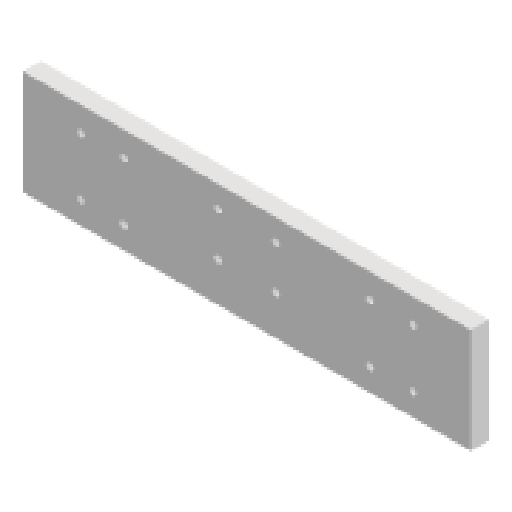
# Autodesk Inventor part: BodyBackLock
Saved by Autodesk Inventor 2025.2 (Build 292293000, 293)
## iProperties
Created: 2025-06-20
Part Number: BodyBackLock
Material: Generic
Document SubType Name: Modeling
Designer: ricoa
Density: 1 g/cm^3
Appearance: Default
Author: ricoa
Autodesk Inventor part; units mm, degrees
ref_plane "YZ Plane" through (0, 0, 0) normal (1, 0, 0) x (0, 1, 0)
ref_plane "XZ Plane" through (0, 0, 0) normal (0, 1, 0) x (-1, 0, 0)
ref_plane "XY Plane" through (0, 0, 0) normal (0, 0, 1) x (1, 0, 0)
sketch "Sketch1" plane through (0, 0, 0) normal (0, 0, 1) x (1, 0, 0)
  line L0 (0, 0) -> (-8, 0)
  line L1 (-8, 0) -> (-8, 8.75)
  circle A0 centre (-8, 8.75) radius 1
  line L2 (0, 0) -> (0, 20.6668)
  line L3 (0, 0) -> (-30.575, 0)
  line L4 (-57, 14.75) -> (57, 14.75)
  line L5 (57, 14.75) -> (57, -14.75)
  line L6 (-57, -14.75) -> (-57, 14.75)
  line L7 (-57, 14.75) -> (57, -14.75) construction
  line L8 (57, 14.75) -> (-57, -14.75) construction
  circle A1 centre (8, 8.75) radius 1
  circle A2 centre (-8, -3.25) radius 1
  circle A3 centre (8, -3.25) radius 1
  line L9 (57, 0) -> (46, 0)
  line L10 (46, 0) -> (46, 8)
  line L11 (46, 8) -> (34, 8)
  circle A4 centre (46, 8) radius 1
  circle A5 centre (34, 8) radius 1
  circle A6 centre (46, -8) radius 1
  circle A7 centre (34, -8) radius 1
  circle A8 centre (-46, 8) radius 1
  circle A9 centre (-34, 8) radius 1
  circle A10 centre (-46, -8) radius 1
  circle A11 centre (-34, -8) radius 1
  line L12 (8, 0) -> (8, -3.25) construction
  line L13 (8, -3.25) -> (-8, -3.25) construction
  line L14 (-8, -3.25) -> (-8, 0)
  line L15 (57, 14.75) -> (62, 14.75) projected
  line L16 (-62, 14.75) -> (-57, 14.75) projected
  line L17 (57, -49.25) -> (57, 14.75) projected
  line L18 (52, -19.25) -> (42, -19.25) projected
  line L19 (42, -19.25) -> (42, -14.25) projected
  line L20 (52, -19.25) -> (52, -14.25) projected
  line L21 (42, -19.25) -> (42, -14.25) projected
  line L22 (52, -19.25) -> (52, -14.25) projected
  line L23 (32, -19.25) -> (22, -19.25) projected
  line L24 (22, -19.25) -> (22, -14.25) projected
  line L25 (32, -19.25) -> (32, -14.25) projected
  line L26 (12, -19.25) -> (2, -19.25) projected
  line L27 (2, -19.25) -> (2, -14.25) projected
  line L28 (12, -19.25) -> (12, -14.25) projected
  line L29 (-22, -19.25) -> (-32, -19.25) projected
  line L30 (-32, -19.25) -> (-32, -14.25) projected
  line L31 (-22, -19.25) -> (-22, -14.25) projected
  line L32 (-42, -19.25) -> (-52, -19.25) projected
  line L33 (-52, -19.25) -> (-52, -14.25) projected
  line L34 (-42, -19.25) -> (-42, -14.25) projected
  line L35 (-57, -49.25) -> (-57, 14.75) projected
  line L36 (12, -19.25) -> (2, -19.25) projected
  line L37 (2, -19.25) -> (2, -14.25) projected
  line L38 (12, -19.25) -> (12, -14.25) projected
  line L39 (32, -19.25) -> (22, -19.25) projected
  line L40 (22, -19.25) -> (22, -14.25) projected
  line L41 (32, -19.25) -> (32, -14.25) projected
  line L42 (52, -19.25) -> (42, -19.25) projected
  line L43 (42, -19.25) -> (42, -14.25) projected
  line L44 (52, -19.25) -> (52, -14.25) projected
  line L45 (52, -14.25) -> (57, -14.25)
  line L46 (42, -14.25) -> (32, -14.25)
  line L47 (22, -14.25) -> (12, -14.25)
  line L48 (2, -14.25) -> (-2, -14.25)
  line L49 (-12, -14.25) -> (-22, -14.25)
  line L50 (-32, -14.25) -> (-42, -14.25)
  line L51 (-52, -14.25) -> (-57, -14.25)
  line L52 (-2, -19.25) -> (-12, -19.25)
  line L53 (57, 14.75) -> (-57, 14.75)
  line L54 (-57, 14.75) -> (-57, -14.25)
  line L55 (-57, -14.25) -> (57, -14.25)
  line L56 (57, -14.25) -> (57, 14.75)
  dimension "d1" = 8.75
  dimension "d2" = 2
  dimension "d5" = 114
  dimension "d7" = 11
  dimension "d8" = 8
  dimension "d9" = 12
  dimension "d10" = 2
  dimension "d11" = 2
  dimension "d21" = 3.25
  constraints: 54 end point, 12 centre point, 7 symmetric about line, 6 horizontal, 6 perpendicular, 5 coincident, 5 collinear, 5 point on line, 4 vertical, 3 midpoint, 3 parallel, 7 other
  measures "d1" distance of L0.end L1.end
  measures "d2" diameter of A0
  measures "d5" distance between parallel lines of L6 L5
  measures "d7" distance of L9.start L9.end
  measures "d8" distance of L9.end L10.end
  measures "d9" distance of L10.end L11.end
  measures "d10" diameter of A4
  measures "d11" diameter of A5
  measures "d21" distance of L12.start L12.end
extrude "Extrusion1" add sketch "Sketch1" along normal blind 5 contours L4 L5 L45 L55 L46 L47 L48 L49 L50 L51 L6
move faces "Move1" translate (5, 0, 0) faces at (57, -4.5833, 1.6667)
move faces "Move2" translate (-5, 0, 0) faces at (-57, 5.0833, 1.6667)
body "Solid1"
